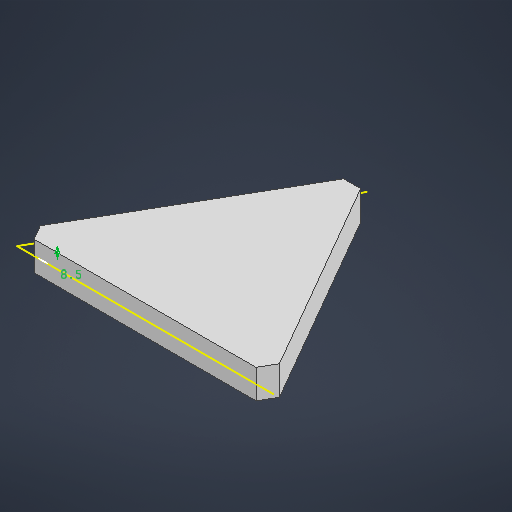
# Autodesk Inventor part: Part4
Saved by Autodesk Inventor 2025.4 (Build 294407000, 407)
## iProperties
Created: 2026-06-25
Part Number: Part4
Material: Generic
Document SubType Name: Modeling
Designer: VuQuan
Density: 1 g/cm^3
Appearance: Default
Author: VuQuan
Autodesk Inventor part; units mm, degrees
ref_plane "YZ Plane" through (0, 0, 0) normal (1, 0, 0) x (0, 1, 0)
ref_plane "XZ Plane" through (0, 0, 0) normal (0, 1, 0) x (-1, 0, 0)
ref_plane "XY Plane" through (0, 0, 0) normal (0, 0, 1) x (1, 0, 0)
sketch "Sketch1" plane through (0, 0, 0) normal (0, 1, 0) x (-1, 0, 0)
  line L0 (0, -86.6025) -> (-75, 43.3013)
  line L1 (-75, 43.3013) -> (75, 43.3013)
  line L2 (75, 43.3013) -> (0, -86.6025)
  line L3 (5, -77.9423) -> (-5, -77.9423)
  line L4 (65, 43.3013) -> (70, 34.641)
  line L5 (-70, 34.641) -> (-65, 43.3013)
  point P0 (0, 0)
  point P1 (-65, 43.3013)
  point P2 (-70, 34.641)
  point P3 (70, 34.641)
  point P4 (65, 43.3013)
  dimension "d1" = 150
  dimension "d2" = 10
  dimension "d5" = 360
  constraints: 12 end point, 2 point on line, 1 horizontal, 1 vertical alignment, 17 other
  measures "d1" distance of L0.end L1.end
  measures "d2" distance of L3.start L3.end
sketch "Sketch2" plane through (0, 0, 0) normal (0, 1, 0) x (-1, 0, 0)
  circle A0 centre (60, 34.641) radius 8.6603
  line L0 (-75, 43.3013) -> (75, 43.3013) projected
  line L1 (65, 43.3013) -> (70, 34.641) projected
  line L2 (75, 43.3013) -> (0, -86.6025) projected
  circle A1 centre (60, 34.641) radius 4.25
  point P0 (0, 0)
  dimension "d7" = 8.5
  constraints: 3 tangent, 2 centre point, 1 coincident
  measures "d7" diameter of A1
extrude "Extrusion1" add sketch "Sketch1" along normal mid plane 17 contours L0 L5 L1 L4 L2 L3
body "Solid1"
